Autodesk Fusion 360 part; units mm, degrees
(part 3 of 7)
sketch "Open core spacer (4)" plane through (0, 0, 40.4) normal (0, 0, 1) x (1, 0, 0) in component "CORE | GuardUpper"
  circle A0 centre (0, 0) radius 3.2
extrude "Open core spacer (1)'''" add sketch "Open core spacer (4)" along normal blind 14.6 separate body makes body 8 in component "CORE | GuardUpper"
ref_plane "WorkPlane2" through (0, 0, 40.4) normal (0, 0, 1) x (1, 0, 0) in component "CORE | GuardUpper"
sketch "Metal through bolt clearance (4)" plane through (0, 0, 40.4) normal (0, 0, 1) x (1, 0, 0) in component "CORE | GuardUpper"
  circle A0 centre (0, 0) radius 1.2
extrude "Metal through bolt clearance (1)'''" cut sketch "Metal through bolt clearance (4)" along normal blind 14.6 bodies 8 in component "CORE | GuardUpper"
ref_plane "WorkPlane1" through (0, 0, 15) normal (0, 0, 1) x (1, 0, 0) in component "CORE | GuardTall"
sketch "Open core spacer (5)" plane through (0, 0, 15) normal (0, 0, 1) x (1, 0, 0) in component "CORE | GuardTall"
  circle A0 centre (0, 0) radius 3.2
extrude "Open core spacer (1)''''" add sketch "Open core spacer (5)" along normal blind 40 separate body makes body 9 in component "CORE | GuardTall"
ref_plane "WorkPlane2" through (0, 0, 15) normal (0, 0, 1) x (1, 0, 0) in component "CORE | GuardTall"
sketch "Metal through bolt clearance (5)" plane through (0, 0, 15) normal (0, 0, 1) x (1, 0, 0) in component "CORE | GuardTall"
  circle A0 centre (0, 0) radius 1.2
extrude "Metal through bolt clearance (1)''''" cut sketch "Metal through bolt clearance (5)" along normal blind 40 bodies 9 in component "CORE | GuardTall"
ref_plane "WorkPlane1" through (0, 0, 38) normal (0, 0, 1) x (1, 0, 0) in component "CORE | CoreBridge"
sketch "Feather board saddle" plane through (0, 0, 38) normal (0, 0, 1) x (1, 0, 0) in component "CORE | CoreBridge"
  line L0 (-27.5, -13.5) -> (27.5, -13.5)
  line L1 (27.5, -13.5) -> (27.5, 13.5)
  line L2 (27.5, 13.5) -> (-27.5, 13.5)
  line L3 (-27.5, 13.5) -> (-27.5, -13.5)
extrude "Feather board saddle (1)" add sketch "Feather board saddle" along normal blind 2.4 separate body makes body 10 in component "CORE | CoreBridge"
ref_plane "WorkPlane2" through (0, 0, 38) normal (0, 0, 1) x (1, 0, 0) in component "CORE | CoreBridge"
sketch "Raised bridge arm outside servo plugs" plane through (0, 0, 38) normal (0, 0, 1) x (1, 0, 0) in component "CORE | CoreBridge"
  line L0 (38.5978, 18.6998) -> (39.1173, 19.354)
  line L1 (39.1173, 19.354) -> (39.4498, 20.1204)
  line L2 (39.4498, 20.1204) -> (39.5726, 20.9466)
  line L3 (39.5726, 20.9466) -> (39.4774, 21.7766)
  line L4 (39.4774, 21.7766) -> (39.1706, 22.5536)
  line L5 (39.1706, 22.5536) -> (38.6732, 23.2247)
  line L6 (38.6732, 23.2247) -> (38.019, 23.7442)
  line L7 (38.019, 23.7442) -> (37.2527, 24.0767)
  line L8 (37.2527, 24.0767) -> (36.4264, 24.1996)
  line L9 (36.4264, 24.1996) -> (35.5965, 24.1043)
  line L10 (35.5965, 24.1043) -> (34.8195, 23.7976)
  line L11 (34.8195, 23.7976) -> (34.1484, 23.3002)
  line L12 (34.1484, 23.3002) -> (22.7753, 12.3002)
  line L13 (22.7753, 12.3002) -> (22.2558, 11.646)
  line L14 (22.2558, 11.646) -> (21.9233, 10.8796)
  line L15 (21.9233, 10.8796) -> (21.8004, 10.0534)
  line L16 (21.8004, 10.0534) -> (21.8957, 9.2234)
  line L17 (21.8957, 9.2234) -> (22.2024, 8.4464)
  line L18 (22.2024, 8.4464) -> (22.6998, 7.7753)
  line L19 (22.6998, 7.7753) -> (23.354, 7.2558)
  line L20 (23.354, 7.2558) -> (24.1204, 6.9233)
  line L21 (24.1204, 6.9233) -> (24.9466, 6.8004)
  line L22 (24.9466, 6.8004) -> (25.7766, 6.8957)
  line L23 (25.7766, 6.8957) -> (26.5536, 7.2024)
  line L24 (26.5536, 7.2024) -> (27.2247, 7.6998)
  line L25 (27.2247, 7.6998) -> (38.5978, 18.6998)
extrude "Raised bridge arm outside servo plugs (1)" add sketch "Raised bridge arm outside servo plugs" along normal blind 2.4 bodies 10 in component "CORE | CoreBridge"
ref_plane "WorkPlane3" through (0, 0, 38) normal (0, 0, 1) x (1, 0, 0) in component "CORE | CoreBridge"
sketch "Raised bridge arm outside servo plugs (1)" plane through (0, 0, 38) normal (0, 0, 1) x (1, 0, 0) in component "CORE | CoreBridge"
  line L0 (-34.1484, 23.3002) -> (-34.8195, 23.7976)
  line L1 (-34.8195, 23.7976) -> (-35.5965, 24.1043)
  line L2 (-35.5965, 24.1043) -> (-36.4264, 24.1996)
  line L3 (-36.4264, 24.1996) -> (-37.2527, 24.0767)
  line L4 (-37.2527, 24.0767) -> (-38.019, 23.7442)
  line L5 (-38.019, 23.7442) -> (-38.6732, 23.2247)
  line L6 (-38.6732, 23.2247) -> (-39.1706, 22.5536)
  line L7 (-39.1706, 22.5536) -> (-39.4774, 21.7766)
  line L8 (-39.4774, 21.7766) -> (-39.5726, 20.9466)
  line L9 (-39.5726, 20.9466) -> (-39.4498, 20.1204)
  line L10 (-39.4498, 20.1204) -> (-39.1173, 19.354)
  line L11 (-39.1173, 19.354) -> (-38.5978, 18.6998)
  line L12 (-38.5978, 18.6998) -> (-27.2247, 7.6998)
  line L13 (-27.2247, 7.6998) -> (-26.5536, 7.2024)
  line L14 (-26.5536, 7.2024) -> (-25.7766, 6.8957)
  line L15 (-25.7766, 6.8957) -> (-24.9466, 6.8004)
  line L16 (-24.9466, 6.8004) -> (-24.1204, 6.9233)
  line L17 (-24.1204, 6.9233) -> (-23.354, 7.2558)
  line L18 (-23.354, 7.2558) -> (-22.6998, 7.7753)
  line L19 (-22.6998, 7.7753) -> (-22.2024, 8.4464)
  line L20 (-22.2024, 8.4464) -> (-21.8957, 9.2234)
  line L21 (-21.8957, 9.2234) -> (-21.8004, 10.0534)
  line L22 (-21.8004, 10.0534) -> (-21.9233, 10.8796)
  line L23 (-21.9233, 10.8796) -> (-22.2558, 11.646)
  line L24 (-22.2558, 11.646) -> (-22.7753, 12.3002)
  line L25 (-22.7753, 12.3002) -> (-34.1484, 23.3002)
extrude "Raised bridge arm outside servo plugs (2)" add sketch "Raised bridge arm outside servo plugs (1)" along normal blind 2.4 bodies 10 in component "CORE | CoreBridge"
ref_plane "WorkPlane4" through (0, 0, 38) normal (0, 0, 1) x (1, 0, 0) in component "CORE | CoreBridge"
sketch "Raised bridge arm outside servo plugs (2)" plane through (0, 0, 38) normal (0, 0, 1) x (1, 0, 0) in component "CORE | CoreBridge"
  line L0 (-38.5978, -18.6998) -> (-39.1173, -19.354)
  line L1 (-39.1173, -19.354) -> (-39.4498, -20.1204)
  line L2 (-39.4498, -20.1204) -> (-39.5726, -20.9466)
  line L3 (-39.5726, -20.9466) -> (-39.4774, -21.7766)
  line L4 (-39.4774, -21.7766) -> (-39.1706, -22.5536)
  line L5 (-39.1706, -22.5536) -> (-38.6732, -23.2247)
  line L6 (-38.6732, -23.2247) -> (-38.019, -23.7442)
  line L7 (-38.019, -23.7442) -> (-37.2527, -24.0767)
  line L8 (-37.2527, -24.0767) -> (-36.4264, -24.1996)
  line L9 (-36.4264, -24.1996) -> (-35.5965, -24.1043)
  line L10 (-35.5965, -24.1043) -> (-34.8195, -23.7976)
  line L11 (-34.8195, -23.7976) -> (-34.1484, -23.3002)
  line L12 (-34.1484, -23.3002) -> (-22.7753, -12.3002)
  line L13 (-22.7753, -12.3002) -> (-22.2558, -11.646)
  line L14 (-22.2558, -11.646) -> (-21.9233, -10.8796)
  line L15 (-21.9233, -10.8796) -> (-21.8004, -10.0534)
  line L16 (-21.8004, -10.0534) -> (-21.8957, -9.2234)
  line L17 (-21.8957, -9.2234) -> (-22.2024, -8.4464)
  line L18 (-22.2024, -8.4464) -> (-22.6998, -7.7753)
  line L19 (-22.6998, -7.7753) -> (-23.354, -7.2558)
  line L20 (-23.354, -7.2558) -> (-24.1204, -6.9233)
  line L21 (-24.1204, -6.9233) -> (-24.9466, -6.8004)
  line L22 (-24.9466, -6.8004) -> (-25.7766, -6.8957)
  line L23 (-25.7766, -6.8957) -> (-26.5536, -7.2024)
  line L24 (-26.5536, -7.2024) -> (-27.2247, -7.6998)
  line L25 (-27.2247, -7.6998) -> (-38.5978, -18.6998)
extrude "Raised bridge arm outside servo plugs (3)" add sketch "Raised bridge arm outside servo plugs (2)" along normal blind 2.4 bodies 10 in component "CORE | CoreBridge"
ref_plane "WorkPlane5" through (0, 0, 38) normal (0, 0, 1) x (1, 0, 0) in component "CORE | CoreBridge"
sketch "Raised bridge arm outside servo plugs (3)" plane through (0, 0, 38) normal (0, 0, 1) x (1, 0, 0) in component "CORE | CoreBridge"
  line L0 (34.1484, -23.3002) -> (34.8195, -23.7976)
  line L1 (34.8195, -23.7976) -> (35.5965, -24.1043)
  line L2 (35.5965, -24.1043) -> (36.4264, -24.1996)
  line L3 (36.4264, -24.1996) -> (37.2527, -24.0767)
  line L4 (37.2527, -24.0767) -> (38.019, -23.7442)
  line L5 (38.019, -23.7442) -> (38.6732, -23.2247)
  line L6 (38.6732, -23.2247) -> (39.1706, -22.5536)
  line L7 (39.1706, -22.5536) -> (39.4774, -21.7766)
  line L8 (39.4774, -21.7766) -> (39.5726, -20.9466)
  line L9 (39.5726, -20.9466) -> (39.4498, -20.1204)
  line L10 (39.4498, -20.1204) -> (39.1173, -19.354)
  line L11 (39.1173, -19.354) -> (38.5978, -18.6998)
  line L12 (38.5978, -18.6998) -> (27.2247, -7.6998)
  line L13 (27.2247, -7.6998) -> (26.5536, -7.2024)
  line L14 (26.5536, -7.2024) -> (25.7766, -6.8957)
  line L15 (25.7766, -6.8957) -> (24.9466, -6.8004)
  line L16 (24.9466, -6.8004) -> (24.1204, -6.9233)
  line L17 (24.1204, -6.9233) -> (23.354, -7.2558)
  line L18 (23.354, -7.2558) -> (22.6998, -7.7753)
  line L19 (22.6998, -7.7753) -> (22.2024, -8.4464)
  line L20 (22.2024, -8.4464) -> (21.8957, -9.2234)
  line L21 (21.8957, -9.2234) -> (21.8004, -10.0534)
  line L22 (21.8004, -10.0534) -> (21.9233, -10.8796)
  line L23 (21.9233, -10.8796) -> (22.2558, -11.646)
  line L24 (22.2558, -11.646) -> (22.7753, -12.3002)
  line L25 (22.7753, -12.3002) -> (34.1484, -23.3002)
extrude "Raised bridge arm outside servo plugs (4)" add sketch "Raised bridge arm outside servo plugs (3)" along normal blind 2.4 bodies 10 in component "CORE | CoreBridge"
ref_plane "WorkPlane6" through (0, 0, 40.4) normal (0, 0, 1) x (1, 0, 0) in component "CORE | CoreBridge"
sketch "Feather exact M2 standoff" plane through (0, 0, 40.4) normal (0, 0, 1) x (1, 0, 0) in component "CORE | CoreBridge"
  circle A0 centre (-22.86, -8.89) radius 2.8
extrude "Feather exact M2 standoff (1)" add sketch "Feather exact M2 standoff" along normal blind 4 bodies 10 in component "CORE | CoreBridge"
ref_plane "WorkPlane7" through (0, 0, 40.4) normal (0, 0, 1) x (1, 0, 0) in component "CORE | CoreBridge"
sketch "Feather exact M2 standoff (1)" plane through (0, 0, 40.4) normal (0, 0, 1) x (1, 0, 0) in component "CORE | CoreBridge"
  circle A0 centre (-22.86, 8.89) radius 2.8
extrude "Feather exact M2 standoff (2)" add sketch "Feather exact M2 standoff (1)" along normal blind 4 bodies 10 in component "CORE | CoreBridge"
ref_plane "WorkPlane8" through (0, 0, 40.4) normal (0, 0, 1) x (1, 0, 0) in component "CORE | CoreBridge"
sketch "Feather exact M2 standoff (2)" plane through (0, 0, 40.4) normal (0, 0, 1) x (1, 0, 0) in component "CORE | CoreBridge"
  circle A0 centre (22.86, -8.89) radius 2.8
extrude "Feather exact M2 standoff (3)" add sketch "Feather exact M2 standoff (2)" along normal blind 4 bodies 10 in component "CORE | CoreBridge"
ref_plane "WorkPlane9" through (0, 0, 40.4) normal (0, 0, 1) x (1, 0, 0) in component "CORE | CoreBridge"
sketch "Feather exact M2 standoff (3)" plane through (0, 0, 40.4) normal (0, 0, 1) x (1, 0, 0) in component "CORE | CoreBridge"
  circle A0 centre (22.86, 8.89) radius 2.8
extrude "Feather exact M2 standoff (4)" add sketch "Feather exact M2 standoff (3)" along normal blind 4 bodies 10 in component "CORE | CoreBridge"
ref_plane "WorkPlane10" through (0, 0, 38) normal (0, 0, 1) x (1, 0, 0) in component "CORE | CoreBridge"
sketch "Separate logic buck cradle" plane through (0, 0, 38) normal (0, 0, 1) x (1, 0, 0) in component "CORE | CoreBridge"
  line L0 (-11, 13) -> (11, 13)
  line L1 (11, 13) -> (11, 29)
  line L2 (11, 29) -> (-11, 29)
  line L3 (-11, 29) -> (-11, 13)
extrude "Separate logic buck cradle (1)" add sketch "Separate logic buck cradle" along normal blind 2.4 bodies 10 in component "CORE | CoreBridge"
ref_plane "WorkPlane11" through (0, 0, 40.4) normal (0, 0, 1) x (1, 0, 0) in component "CORE | CoreBridge"
sketch "Logic buck side rail" plane through (0, 0, 40.4) normal (0, 0, 1) x (1, 0, 0) in component "CORE | CoreBridge"
  line L0 (-10.9, 14.4) -> (-8.9, 14.4)
  line L1 (-8.9, 14.4) -> (-8.9, 28.6)
  line L2 (-8.9, 28.6) -> (-10.9, 28.6)
  line L3 (-10.9, 28.6) -> (-10.9, 14.4)
extrude "Logic buck side rail (1)" add sketch "Logic buck side rail" along normal blind 2 bodies 10 in component "CORE | CoreBridge"
ref_plane "WorkPlane12" through (0, 0, 40.4) normal (0, 0, 1) x (1, 0, 0) in component "CORE | CoreBridge"
sketch "Logic buck side rail (1)" plane through (0, 0, 40.4) normal (0, 0, 1) x (1, 0, 0) in component "CORE | CoreBridge"
  line L0 (8.9, 14.4) -> (10.9, 14.4)
  line L1 (10.9, 14.4) -> (10.9, 28.6)
  line L2 (10.9, 28.6) -> (8.9, 28.6)
  line L3 (8.9, 28.6) -> (8.9, 14.4)
extrude "Logic buck side rail (2)" add sketch "Logic buck side rail (1)" along normal blind 2 bodies 10 in component "CORE | CoreBridge"
ref_plane "WorkPlane13" through (0, 0, 38) normal (0, 0, 1) x (1, 0, 0) in component "CORE | CoreBridge"
sketch "Vent slots and logic buck retaining strap" plane through (0, 0, 38) normal (0, 0, 1) x (1, 0, 0) in component "CORE | CoreBridge"
  circle A0 centre (36.3731, 21) radius 1.2
  circle A1 centre (-36.3731, 21) radius 1.2
  circle A2 centre (-36.3731, -21) radius 1.2
  circle A3 centre (36.3731, -21) radius 1.2
  line L0 (17, -4) -> (18.0353, -3.8637)
  line L1 (18.0353, -3.8637) -> (19, -3.4641)
  line L2 (19, -3.4641) -> (19.8284, -2.8284)
  line L3 (19.8284, -2.8284) -> (20.4641, -2)
  line L4 (20.4641, -2) -> (20.8637, -1.0353)
  line L5 (20.8637, -1.0353) -> (21, 0)
  line L6 (21, 0) -> (20.8637, 1.0353)
  line L7 (20.8637, 1.0353) -> (20.4641, 2)
  line L8 (20.4641, 2) -> (19.8284, 2.8284)
  line L9 (19.8284, 2.8284) -> (19, 3.4641)
  line L10 (19, 3.4641) -> (18.0353, 3.8637)
  line L11 (18.0353, 3.8637) -> (17, 4)
  line L12 (17, 4) -> (-17, 4)
  line L13 (-17, 4) -> (-18.0353, 3.8637)
  line L14 (-18.0353, 3.8637) -> (-19, 3.4641)
  line L15 (-19, 3.4641) -> (-19.8284, 2.8284)
  line L16 (-19.8284, 2.8284) -> (-20.4641, 2)
  line L17 (-20.4641, 2) -> (-20.8637, 1.0353)
  line L18 (-20.8637, 1.0353) -> (-21, 0)
  line L19 (-21, 0) -> (-20.8637, -1.0353)
  line L20 (-20.8637, -1.0353) -> (-20.4641, -2)
  line L21 (-20.4641, -2) -> (-19.8284, -2.8284)
  line L22 (-19.8284, -2.8284) -> (-19, -3.4641)
  line L23 (-19, -3.4641) -> (-18.0353, -3.8637)
  line L24 (-18.0353, -3.8637) -> (-17, -4)
  line L25 (-17, -4) -> (17, -4)
  line L26 (8, 24.8) -> (8.3106, 24.8409)
  line L27 (8.3106, 24.8409) -> (8.6, 24.9608)
  line L28 (8.6, 24.9608) -> (8.8485, 25.1515)
  line L29 (8.8485, 25.1515) -> (9.0392, 25.4)
  line L30 (9.0392, 25.4) -> (9.1591, 25.6894)
  line L31 (9.1591, 25.6894) -> (9.2, 26)
  line L32 (9.2, 26) -> (9.1591, 26.3106)
  line L33 (9.1591, 26.3106) -> (9.0392, 26.6)
  line L34 (9.0392, 26.6) -> (8.8485, 26.8485)
  line L35 (8.8485, 26.8485) -> (8.6, 27.0392)
  line L36 (8.6, 27.0392) -> (8.3106, 27.1591)
  line L37 (8.3106, 27.1591) -> (8, 27.2)
  line L38 (8, 27.2) -> (-8, 27.2)
  line L39 (-8, 27.2) -> (-8.3106, 27.1591)
  line L40 (-8.3106, 27.1591) -> (-8.6, 27.0392)
  line L41 (-8.6, 27.0392) -> (-8.8485, 26.8485)
  line L42 (-8.8485, 26.8485) -> (-9.0392, 26.6)
  line L43 (-9.0392, 26.6) -> (-9.1591, 26.3106)
  line L44 (-9.1591, 26.3106) -> (-9.2, 26)
  line L45 (-9.2, 26) -> (-9.1591, 25.6894)
  line L46 (-9.1591, 25.6894) -> (-9.0392, 25.4)
  line L47 (-9.0392, 25.4) -> (-8.8485, 25.1515)
  line L48 (-8.8485, 25.1515) -> (-8.6, 24.9608)
  line L49 (-8.6, 24.9608) -> (-8.3106, 24.8409)
  line L50 (-8.3106, 24.8409) -> (-8, 24.8)
  line L51 (-8, 24.8) -> (8, 24.8)
extrude "Vent slots and logic buck retaining strap (1)" cut sketch "Vent slots and logic buck retaining strap" along normal blind 2.4 bodies 10 in component "CORE | CoreBridge"
ref_plane "WorkPlane14" through (0, 0, 38) normal (0, 0, 1) x (1, 0, 0) in component "CORE | CoreBridge"
sketch "Feather M2 through holes" plane through (0, 0, 38) normal (0, 0, 1) x (1, 0, 0) in component "CORE | CoreBridge"
  circle A0 centre (-22.86, -8.89) radius 1.2
  circle A1 centre (-22.86, 8.89) radius 1.2
  circle A2 centre (22.86, -8.89) radius 1.2
  circle A3 centre (22.86, 8.89) radius 1.2
extrude "Feather M2 through holes (1)" cut sketch "Feather M2 through holes" along normal blind 6.4 bodies 10 in component "CORE | CoreBridge"
ref_plane "WorkPlane1" through (0, 0, 55) normal (0, 0, 1) x (1, 0, 0) in component "CORE | CoreCap"
sketch "Removable protective top" plane through (0, 0, 55) normal (0, 0, 1) x (1, 0, 0) in component "CORE | CoreCap"
  line L0 (43.5, 0) -> (43.1279, 5.7432)
  line L1 (43.1279, 5.7432) -> (42.0178, 11.388)
  line L2 (42.0178, 11.388) -> (40.1888, 16.8381)
  line L3 (40.1888, 16.8381) -> (37.6721, 22)
  line L4 (37.6721, 22) -> (34.5109, 26.7855)
  line L5 (34.5109, 26.7855) -> (30.7591, 31.1127)
  line L6 (30.7591, 31.1127) -> (26.4811, 34.9075)
  line L7 (26.4811, 34.9075) -> (21.75, 38.1051)
  line L8 (21.75, 38.1051) -> (16.6467, 40.6507)
  line L9 (16.6467, 40.6507) -> (11.2586, 42.5007)
  line L10 (11.2586, 42.5007) -> (5.6779, 43.6236)
  line L11 (5.6779, 43.6236) -> (0, 44)
  line L12 (0, 44) -> (-5.6779, 43.6236)
  line L13 (-5.6779, 43.6236) -> (-11.2586, 42.5007)
  line L14 (-11.2586, 42.5007) -> (-16.6467, 40.6507)
  line L15 (-16.6467, 40.6507) -> (-21.75, 38.1051)
  line L16 (-21.75, 38.1051) -> (-26.4811, 34.9075)
  line L17 (-26.4811, 34.9075) -> (-30.7591, 31.1127)
  line L18 (-30.7591, 31.1127) -> (-34.5109, 26.7855)
  line L19 (-34.5109, 26.7855) -> (-37.6721, 22)
  line L20 (-37.6721, 22) -> (-40.1888, 16.8381)
  line L21 (-40.1888, 16.8381) -> (-42.0178, 11.388)
  line L22 (-42.0178, 11.388) -> (-43.1279, 5.7432)
  line L23 (-43.1279, 5.7432) -> (-43.5, 0)
  line L24 (-43.5, 0) -> (-43.1279, -5.7432)
  line L25 (-43.1279, -5.7432) -> (-42.0178, -11.388)
  line L26 (-42.0178, -11.388) -> (-40.1888, -16.8381)
  line L27 (-40.1888, -16.8381) -> (-37.6721, -22)
  line L28 (-37.6721, -22) -> (-34.5109, -26.7855)
  line L29 (-34.5109, -26.7855) -> (-30.7591, -31.1127)
  line L30 (-30.7591, -31.1127) -> (-26.4811, -34.9075)
  line L31 (-26.4811, -34.9075) -> (-21.75, -38.1051)
  line L32 (-21.75, -38.1051) -> (-16.6467, -40.6507)
  line L33 (-16.6467, -40.6507) -> (-11.2586, -42.5007)
  line L34 (-11.2586, -42.5007) -> (-5.6779, -43.6236)
  line L35 (-5.6779, -43.6236) -> (0, -44)
  line L36 (0, -44) -> (5.6779, -43.6236)
  line L37 (5.6779, -43.6236) -> (11.2586, -42.5007)
  line L38 (11.2586, -42.5007) -> (16.6467, -40.6507)
  line L39 (16.6467, -40.6507) -> (21.75, -38.1051)
  line L40 (21.75, -38.1051) -> (26.4811, -34.9075)
  line L41 (26.4811, -34.9075) -> (30.7591, -31.1127)
  line L42 (30.7591, -31.1127) -> (34.5109, -26.7855)
  line L43 (34.5109, -26.7855) -> (37.6721, -22)
  line L44 (37.6721, -22) -> (40.1888, -16.8381)
  line L45 (40.1888, -16.8381) -> (42.0178, -11.388)
  line L46 (42.0178, -11.388) -> (43.1279, -5.7432)
  line L47 (43.1279, -5.7432) -> (43.5, 0)
extrude "Removable protective top (1)" add sketch "Removable protective top" along normal blind 2.4 separate body makes body 11 in component "CORE | CoreCap"
ref_plane "WorkPlane2" through (0, 0, 55) normal (0, 0, 1) x (1, 0, 0) in component "CORE | CoreCap"
sketch "Parallel ventilation slots" plane through (0, 0, 55) normal (0, 0, 1) x (1, 0, 0) in component "CORE | CoreCap"
  line L0 (23, -29.6) -> (23.4141, -29.5455)
  line L1 (23.4141, -29.5455) -> (23.8, -29.3856)
  line L2 (23.8, -29.3856) -> (24.1314, -29.1314)
  line L3 (24.1314, -29.1314) -> (24.3856, -28.8)
  line L4 (24.3856, -28.8) -> (24.5455, -28.4141)
  line L5 (24.5455, -28.4141) -> (24.6, -28)
  line L6 (24.6, -28) -> (24.5455, -27.5859)
  line L7 (24.5455, -27.5859) -> (24.3856, -27.2)
  line L8 (24.3856, -27.2) -> (24.1314, -26.8686)
  line L9 (24.1314, -26.8686) -> (23.8, -26.6144)
  line L10 (23.8, -26.6144) -> (23.4141, -26.4545)
  line L11 (23.4141, -26.4545) -> (23, -26.4)
  line L12 (23, -26.4) -> (-23, -26.4)
  line L13 (-23, -26.4) -> (-23.4141, -26.4545)
  line L14 (-23.4141, -26.4545) -> (-23.8, -26.6144)
  line L15 (-23.8, -26.6144) -> (-24.1314, -26.8686)
  line L16 (-24.1314, -26.8686) -> (-24.3856, -27.2)
  line L17 (-24.3856, -27.2) -> (-24.5455, -27.5859)
  line L18 (-24.5455, -27.5859) -> (-24.6, -28)
  line L19 (-24.6, -28) -> (-24.5455, -28.4141)
  line L20 (-24.5455, -28.4141) -> (-24.3856, -28.8)
  line L21 (-24.3856, -28.8) -> (-24.1314, -29.1314)
  line L22 (-24.1314, -29.1314) -> (-23.8, -29.3856)
  line L23 (-23.8, -29.3856) -> (-23.4141, -29.5455)
  line L24 (-23.4141, -29.5455) -> (-23, -29.6)
  line L25 (-23, -29.6) -> (23, -29.6)
extrude "Parallel ventilation slots (1)" cut sketch "Parallel ventilation slots" along normal blind 2.4 bodies 11 in component "CORE | CoreCap"
ref_plane "WorkPlane3" through (0, 0, 55) normal (0, 0, 1) x (1, 0, 0) in component "CORE | CoreCap"
sketch "Parallel ventilation slots (1)" plane through (0, 0, 55) normal (0, 0, 1) x (1, 0, 0) in component "CORE | CoreCap"
  line L0 (28, -21.6) -> (28.4141, -21.5455)
  line L1 (28.4141, -21.5455) -> (28.8, -21.3856)
  line L2 (28.8, -21.3856) -> (29.1314, -21.1314)
  line L3 (29.1314, -21.1314) -> (29.3856, -20.8)
  line L4 (29.3856, -20.8) -> (29.5455, -20.4141)
  line L5 (29.5455, -20.4141) -> (29.6, -20)
  line L6 (29.6, -20) -> (29.5455, -19.5859)
  line L7 (29.5455, -19.5859) -> (29.3856, -19.2)
  line L8 (29.3856, -19.2) -> (29.1314, -18.8686)
  line L9 (29.1314, -18.8686) -> (28.8, -18.6144)
  line L10 (28.8, -18.6144) -> (28.4141, -18.4545)
  line L11 (28.4141, -18.4545) -> (28, -18.4)
  line L12 (28, -18.4) -> (-28, -18.4)
  line L13 (-28, -18.4) -> (-28.4141, -18.4545)
  line L14 (-28.4141, -18.4545) -> (-28.8, -18.6144)
  line L15 (-28.8, -18.6144) -> (-29.1314, -18.8686)
  line L16 (-29.1314, -18.8686) -> (-29.3856, -19.2)
  line L17 (-29.3856, -19.2) -> (-29.5455, -19.5859)
  line L18 (-29.5455, -19.5859) -> (-29.6, -20)
  line L19 (-29.6, -20) -> (-29.5455, -20.4141)
  line L20 (-29.5455, -20.4141) -> (-29.3856, -20.8)
  line L21 (-29.3856, -20.8) -> (-29.1314, -21.1314)
  line L22 (-29.1314, -21.1314) -> (-28.8, -21.3856)
  line L23 (-28.8, -21.3856) -> (-28.4141, -21.5455)
  line L24 (-28.4141, -21.5455) -> (-28, -21.6)
  line L25 (-28, -21.6) -> (28, -21.6)
extrude "Parallel ventilation slots (2)" cut sketch "Parallel ventilation slots (1)" along normal blind 2.4 bodies 11 in component "CORE | CoreCap"
ref_plane "WorkPlane4" through (0, 0, 55) normal (0, 0, 1) x (1, 0, 0) in component "CORE | CoreCap"
sketch "Parallel ventilation slots (2)" plane through (0, 0, 55) normal (0, 0, 1) x (1, 0, 0) in component "CORE | CoreCap"
  line L0 (28, -13.6) -> (28.4141, -13.5455)
  line L1 (28.4141, -13.5455) -> (28.8, -13.3856)
  line L2 (28.8, -13.3856) -> (29.1314, -13.1314)
  line L3 (29.1314, -13.1314) -> (29.3856, -12.8)
  line L4 (29.3856, -12.8) -> (29.5455, -12.4141)
  line L5 (29.5455, -12.4141) -> (29.6, -12)
  line L6 (29.6, -12) -> (29.5455, -11.5859)
  line L7 (29.5455, -11.5859) -> (29.3856, -11.2)
  line L8 (29.3856, -11.2) -> (29.1314, -10.8686)
  line L9 (29.1314, -10.8686) -> (28.8, -10.6144)
  line L10 (28.8, -10.6144) -> (28.4141, -10.4545)
  line L11 (28.4141, -10.4545) -> (28, -10.4)
  line L12 (28, -10.4) -> (-28, -10.4)
  line L13 (-28, -10.4) -> (-28.4141, -10.4545)
  line L14 (-28.4141, -10.4545) -> (-28.8, -10.6144)
  line L15 (-28.8, -10.6144) -> (-29.1314, -10.8686)
  line L16 (-29.1314, -10.8686) -> (-29.3856, -11.2)
  line L17 (-29.3856, -11.2) -> (-29.5455, -11.5859)
  line L18 (-29.5455, -11.5859) -> (-29.6, -12)
  line L19 (-29.6, -12) -> (-29.5455, -12.4141)
  line L20 (-29.5455, -12.4141) -> (-29.3856, -12.8)
  line L21 (-29.3856, -12.8) -> (-29.1314, -13.1314)
  line L22 (-29.1314, -13.1314) -> (-28.8, -13.3856)
  line L23 (-28.8, -13.3856) -> (-28.4141, -13.5455)
  line L24 (-28.4141, -13.5455) -> (-28, -13.6)
  line L25 (-28, -13.6) -> (28, -13.6)
extrude "Parallel ventilation slots (3)" cut sketch "Parallel ventilation slots (2)" along normal blind 2.4 bodies 11 in component "CORE | CoreCap"
ref_plane "WorkPlane5" through (0, 0, 55) normal (0, 0, 1) x (1, 0, 0) in component "CORE | CoreCap"
sketch "Parallel ventilation slots (3)" plane through (0, 0, 55) normal (0, 0, 1) x (1, 0, 0) in component "CORE | CoreCap"
  line L0 (28, -1.6) -> (28.4141, -1.5455)
  line L1 (28.4141, -1.5455) -> (28.8, -1.3856)
  line L2 (28.8, -1.3856) -> (29.1314, -1.1314)
  line L3 (29.1314, -1.1314) -> (29.3856, -0.8)
  line L4 (29.3856, -0.8) -> (29.5455, -0.4141)
  line L5 (29.5455, -0.4141) -> (29.6, 0)
  line L6 (29.6, 0) -> (29.5455, 0.4141)
  line L7 (29.5455, 0.4141) -> (29.3856, 0.8)
  line L8 (29.3856, 0.8) -> (29.1314, 1.1314)
  line L9 (29.1314, 1.1314) -> (28.8, 1.3856)
  line L10 (28.8, 1.3856) -> (28.4141, 1.5455)
  line L11 (28.4141, 1.5455) -> (28, 1.6)
  line L12 (28, 1.6) -> (-28, 1.6)
  line L13 (-28, 1.6) -> (-28.4141, 1.5455)
  line L14 (-28.4141, 1.5455) -> (-28.8, 1.3856)
  line L15 (-28.8, 1.3856) -> (-29.1314, 1.1314)
  line L16 (-29.1314, 1.1314) -> (-29.3856, 0.8)
  line L17 (-29.3856, 0.8) -> (-29.5455, 0.4141)
  line L18 (-29.5455, 0.4141) -> (-29.6, 0)
  line L19 (-29.6, 0) -> (-29.5455, -0.4141)
  line L20 (-29.5455, -0.4141) -> (-29.3856, -0.8)
  line L21 (-29.3856, -0.8) -> (-29.1314, -1.1314)
  line L22 (-29.1314, -1.1314) -> (-28.8, -1.3856)
  line L23 (-28.8, -1.3856) -> (-28.4141, -1.5455)
  line L24 (-28.4141, -1.5455) -> (-28, -1.6)
  line L25 (-28, -1.6) -> (28, -1.6)
extrude "Parallel ventilation slots (4)" cut sketch "Parallel ventilation slots (3)" along normal blind 2.4 bodies 11 in component "CORE | CoreCap"
ref_plane "WorkPlane6" through (0, 0, 55) normal (0, 0, 1) x (1, 0, 0) in component "CORE | CoreCap"
sketch "Parallel ventilation slots (4)" plane through (0, 0, 55) normal (0, 0, 1) x (1, 0, 0) in component "CORE | CoreCap"
  line L0 (28, 10.4) -> (28.4141, 10.4545)
  line L1 (28.4141, 10.4545) -> (28.8, 10.6144)
  line L2 (28.8, 10.6144) -> (29.1314, 10.8686)
  line L3 (29.1314, 10.8686) -> (29.3856, 11.2)
  line L4 (29.3856, 11.2) -> (29.5455, 11.5859)
  line L5 (29.5455, 11.5859) -> (29.6, 12)
  line L6 (29.6, 12) -> (29.5455, 12.4141)
  line L7 (29.5455, 12.4141) -> (29.3856, 12.8)
  line L8 (29.3856, 12.8) -> (29.1314, 13.1314)
  line L9 (29.1314, 13.1314) -> (28.8, 13.3856)
  line L10 (28.8, 13.3856) -> (28.4141, 13.5455)
  line L11 (28.4141, 13.5455) -> (28, 13.6)
  line L12 (28, 13.6) -> (-28, 13.6)
  line L13 (-28, 13.6) -> (-28.4141, 13.5455)
  line L14 (-28.4141, 13.5455) -> (-28.8, 13.3856)
  line L15 (-28.8, 13.3856) -> (-29.1314, 13.1314)
  line L16 (-29.1314, 13.1314) -> (-29.3856, 12.8)
  line L17 (-29.3856, 12.8) -> (-29.5455, 12.4141)
  line L18 (-29.5455, 12.4141) -> (-29.6, 12)
  line L19 (-29.6, 12) -> (-29.5455, 11.5859)
  line L20 (-29.5455, 11.5859) -> (-29.3856, 11.2)
  line L21 (-29.3856, 11.2) -> (-29.1314, 10.8686)
  line L22 (-29.1314, 10.8686) -> (-28.8, 10.6144)
  line L23 (-28.8, 10.6144) -> (-28.4141, 10.4545)
  line L24 (-28.4141, 10.4545) -> (-28, 10.4)
  line L25 (-28, 10.4) -> (28, 10.4)
extrude "Parallel ventilation slots (5)" cut sketch "Parallel ventilation slots (4)" along normal blind 2.4 bodies 11 in component "CORE | CoreCap"
ref_plane "WorkPlane7" through (0, 0, 55) normal (0, 0, 1) x (1, 0, 0) in component "CORE | CoreCap"
sketch "Parallel ventilation slots (5)" plane through (0, 0, 55) normal (0, 0, 1) x (1, 0, 0) in component "CORE | CoreCap"
  line L0 (28, 18.4) -> (28.4141, 18.4545)
  line L1 (28.4141, 18.4545) -> (28.8, 18.6144)
  line L2 (28.8, 18.6144) -> (29.1314, 18.8686)
  line L3 (29.1314, 18.8686) -> (29.3856, 19.2)
  line L4 (29.3856, 19.2) -> (29.5455, 19.5859)
  line L5 (29.5455, 19.5859) -> (29.6, 20)
  line L6 (29.6, 20) -> (29.5455, 20.4141)
  line L7 (29.5455, 20.4141) -> (29.3856, 20.8)
  line L8 (29.3856, 20.8) -> (29.1314, 21.1314)
  line L9 (29.1314, 21.1314) -> (28.8, 21.3856)
  line L10 (28.8, 21.3856) -> (28.4141, 21.5455)
  line L11 (28.4141, 21.5455) -> (28, 21.6)
  line L12 (28, 21.6) -> (-28, 21.6)
  line L13 (-28, 21.6) -> (-28.4141, 21.5455)
  line L14 (-28.4141, 21.5455) -> (-28.8, 21.3856)
  line L15 (-28.8, 21.3856) -> (-29.1314, 21.1314)
  line L16 (-29.1314, 21.1314) -> (-29.3856, 20.8)
  line L17 (-29.3856, 20.8) -> (-29.5455, 20.4141)
  line L18 (-29.5455, 20.4141) -> (-29.6, 20)
  line L19 (-29.6, 20) -> (-29.5455, 19.5859)
  line L20 (-29.5455, 19.5859) -> (-29.3856, 19.2)
  line L21 (-29.3856, 19.2) -> (-29.1314, 18.8686)
  line L22 (-29.1314, 18.8686) -> (-28.8, 18.6144)
  line L23 (-28.8, 18.6144) -> (-28.4141, 18.4545)
  line L24 (-28.4141, 18.4545) -> (-28, 18.4)
  line L25 (-28, 18.4) -> (28, 18.4)
extrude "Parallel ventilation slots (6)" cut sketch "Parallel ventilation slots (5)" along normal blind 2.4 bodies 11 in component "CORE | CoreCap"
ref_plane "WorkPlane8" through (0, 0, 55) normal (0, 0, 1) x (1, 0, 0) in component "CORE | CoreCap"
sketch "Parallel ventilation slots (6)" plane through (0, 0, 55) normal (0, 0, 1) x (1, 0, 0) in component "CORE | CoreCap"
  line L0 (23, 26.4) -> (23.4141, 26.4545)
  line L1 (23.4141, 26.4545) -> (23.8, 26.6144)
  line L2 (23.8, 26.6144) -> (24.1314, 26.8686)
  line L3 (24.1314, 26.8686) -> (24.3856, 27.2)
  line L4 (24.3856, 27.2) -> (24.5455, 27.5859)
  line L5 (24.5455, 27.5859) -> (24.6, 28)
  line L6 (24.6, 28) -> (24.5455, 28.4141)
  line L7 (24.5455, 28.4141) -> (24.3856, 28.8)
  line L8 (24.3856, 28.8) -> (24.1314, 29.1314)
  line L9 (24.1314, 29.1314) -> (23.8, 29.3856)
  line L10 (23.8, 29.3856) -> (23.4141, 29.5455)
  line L11 (23.4141, 29.5455) -> (23, 29.6)
  line L12 (23, 29.6) -> (-23, 29.6)
  line L13 (-23, 29.6) -> (-23.4141, 29.5455)
  line L14 (-23.4141, 29.5455) -> (-23.8, 29.3856)
  line L15 (-23.8, 29.3856) -> (-24.1314, 29.1314)
  line L16 (-24.1314, 29.1314) -> (-24.3856, 28.8)
  line L17 (-24.3856, 28.8) -> (-24.5455, 28.4141)
  line L18 (-24.5455, 28.4141) -> (-24.6, 28)
  line L19 (-24.6, 28) -> (-24.5455, 27.5859)
  line L20 (-24.5455, 27.5859) -> (-24.3856, 27.2)
  line L21 (-24.3856, 27.2) -> (-24.1314, 26.8686)
  line L22 (-24.1314, 26.8686) -> (-23.8, 26.6144)
  line L23 (-23.8, 26.6144) -> (-23.4141, 26.4545)
  line L24 (-23.4141, 26.4545) -> (-23, 26.4)
  line L25 (-23, 26.4) -> (23, 26.4)
extrude "Parallel ventilation slots (7)" cut sketch "Parallel ventilation slots (6)" along normal blind 2.4 bodies 11 in component "CORE | CoreCap"
ref_plane "WorkPlane9" through (0, 0, 55) normal (0, 0, 1) x (1, 0, 0) in component "CORE | CoreCap"
sketch "Removable M2x50 guard fasteners" plane through (0, 0, 55) normal (0, 0, 1) x (1, 0, 0) in component "CORE | CoreCap"
  circle A0 centre (36.3731, 21) radius 1.2
  circle A1 centre (0, 42) radius 1.2
  circle A2 centre (-36.3731, 21) radius 1.2
  circle A3 centre (-36.3731, -21) radius 1.2
  circle A4 centre (0, -42) radius 1.2
  circle A5 centre (36.3731, -21) radius 1.2
extrude "Removable M2x50 guard fasteners (1)" cut sketch "Removable M2x50 guard fasteners" along normal blind 2.4 bodies 11 in component "CORE | CoreCap"
ref_plane "WorkPlane1" through (0, 0, 4) normal (0, 0, 1) x (1, 0, 0) in component "03 | Coxa yaw plate"
sketch "Rounded coxa hub" plane through (0, 0, 4) normal (0, 0, 1) x (1, 0, 0) in component "03 | Coxa yaw plate"
  circle A0 centre (0, 0) radius 13.5
extrude "Rounded coxa hub (1)" add sketch "Rounded coxa hub" along normal blind 3 separate body makes body 12 in component "03 | Coxa yaw plate"
ref_plane "WorkPlane2" through (0, 0, 4) normal (0, 0, 1) x (1, 0, 0) in component "03 | Coxa yaw plate"
sketch "Tapered coxa carrier" plane through (0, 0, 4) normal (0, 0, 1) x (1, 0, 0) in component "03 | Coxa yaw plate"
  line L0 (0, -13.5) -> (15, -12)
  line L1 (15, -12) -> (46, -8.5)
  line L2 (46, -8.5) -> (46, 8.5)
  line L3 (46, 8.5) -> (15, 12)
  line L4 (15, 12) -> (0, 13.5)
  line L5 (0, 13.5) -> (0, -13.5)
extrude "Tapered coxa carrier (1)" add sketch "Tapered coxa carrier" along normal blind 3 bodies 12 in component "03 | Coxa yaw plate"
ref_plane "WorkPlane3" through (0, 0, 4) normal (0, 0, 1) x (1, 0, 0) in component "03 | Coxa yaw plate"
sketch "Stock horn screw access and adjustable M2 slots" plane through (0, 0, 4) normal (0, 0, 1) x (1, 0, 0) in component "03 | Coxa yaw plate"
  circle A0 centre (0, 0) radius 2.6
  line L0 (10.7, -1.2) -> (11.0106, -1.1591)
  line L1 (11.0106, -1.1591) -> (11.3, -1.0392)
  line L2 (11.3, -1.0392) -> (11.5485, -0.8485)
  line L3 (11.5485, -0.8485) -> (11.7392, -0.6)
  line L4 (11.7392, -0.6) -> (11.8591, -0.3106)
  line L5 (11.8591, -0.3106) -> (11.9, 0)
  line L6 (11.9, 0) -> (11.8591, 0.3106)
  line L7 (11.8591, 0.3106) -> (11.7392, 0.6)
  line L8 (11.7392, 0.6) -> (11.5485, 0.8485)
  line L9 (11.5485, 0.8485) -> (11.3, 1.0392)
  line L10 (11.3, 1.0392) -> (11.0106, 1.1591)
  line L11 (11.0106, 1.1591) -> (10.7, 1.2)
  line L12 (10.7, 1.2) -> (6.8, 1.2)
  line L13 (6.8, 1.2) -> (6.4894, 1.1591)
  line L14 (6.4894, 1.1591) -> (6.2, 1.0392)
  line L15 (6.2, 1.0392) -> (5.9515, 0.8485)
  line L16 (5.9515, 0.8485) -> (5.7608, 0.6)
  line L17 (5.7608, 0.6) -> (5.6409, 0.3106)
  line L18 (5.6409, 0.3106) -> (5.6, 0)
  line L19 (5.6, 0) -> (5.6409, -0.3106)
  line L20 (5.6409, -0.3106) -> (5.7608, -0.6)
  line L21 (5.7608, -0.6) -> (5.9515, -0.8485)
  line L22 (5.9515, -0.8485) -> (6.2, -1.0392)
  line L23 (6.2, -1.0392) -> (6.4894, -1.1591)
  line L24 (6.4894, -1.1591) -> (6.8, -1.2)
  line L25 (6.8, -1.2) -> (10.7, -1.2)
  line L26 (-6.8, -1.2) -> (-6.4894, -1.1591)
  line L27 (-6.4894, -1.1591) -> (-6.2, -1.0392)
  line L28 (-6.2, -1.0392) -> (-5.9515, -0.8485)
  line L29 (-5.9515, -0.8485) -> (-5.7608, -0.6)
  line L30 (-5.7608, -0.6) -> (-5.6409, -0.3106)
  line L31 (-5.6409, -0.3106) -> (-5.6, 0)
  line L32 (-5.6, 0) -> (-5.6409, 0.3106)
  line L33 (-5.6409, 0.3106) -> (-5.7608, 0.6)
  line L34 (-5.7608, 0.6) -> (-5.9515, 0.8485)
  line L35 (-5.9515, 0.8485) -> (-6.2, 1.0392)
  line L36 (-6.2, 1.0392) -> (-6.4894, 1.1591)
  line L37 (-6.4894, 1.1591) -> (-6.8, 1.2)
  line L38 (-6.8, 1.2) -> (-10.7, 1.2)
  line L39 (-10.7, 1.2) -> (-11.0106, 1.1591)
  line L40 (-11.0106, 1.1591) -> (-11.3, 1.0392)
  line L41 (-11.3, 1.0392) -> (-11.5485, 0.8485)
  line L42 (-11.5485, 0.8485) -> (-11.7392, 0.6)
  line L43 (-11.7392, 0.6) -> (-11.8591, 0.3106)
  line L44 (-11.8591, 0.3106) -> (-11.9, 0)
  line L45 (-11.9, 0) -> (-11.8591, -0.3106)
  line L46 (-11.8591, -0.3106) -> (-11.7392, -0.6)
  line L47 (-11.7392, -0.6) -> (-11.5485, -0.8485)
  line L48 (-11.5485, -0.8485) -> (-11.3, -1.0392)
  line L49 (-11.3, -1.0392) -> (-11.0106, -1.1591)
  line L50 (-11.0106, -1.1591) -> (-10.7, -1.2)
  line L51 (-10.7, -1.2) -> (-6.8, -1.2)
extrude "Stock horn screw access and adjustable M2 slots (1)" cut sketch "Stock horn screw access and adjustable M2 slots" along normal blind 3 bodies 12 in component "03 | Coxa yaw plate"
ref_plane "WorkPlane4" through (0, 0, 4) normal (0, 0, 1) x (1, 0, 0) in component "03 | Coxa yaw plate"
sketch "Hip bracket bolts and lightening" plane through (0, 0, 4) normal (0, 0, 1) x (1, 0, 0) in component "03 | Coxa yaw plate"
  circle A0 centre (17, 4) radius 1.7
  circle A1 centre (42, 4) radius 1.7
  line L0 (35, -8.5) -> (35.647, -8.4148)
  line L1 (35.647, -8.4148) -> (36.25, -8.1651)
  line L2 (36.25, -8.1651) -> (36.7678, -7.7678)
  line L3 (36.7678, -7.7678) -> (37.1651, -7.25)
  line L4 (37.1651, -7.25) -> (37.4148, -6.647)
  line L5 (37.4148, -6.647) -> (37.5, -6)
  line L6 (37.5, -6) -> (37.4148, -5.353)
  line L7 (37.4148, -5.353) -> (37.1651, -4.75)
  line L8 (37.1651, -4.75) -> (36.7678, -4.2322)
  line L9 (36.7678, -4.2322) -> (36.25, -3.8349)
  line L10 (36.25, -3.8349) -> (35.647, -3.5852)
  line L11 (35.647, -3.5852) -> (35, -3.5)
  line L12 (35, -3.5) -> (16, -3.5)
  line L13 (16, -3.5) -> (15.353, -3.5852)
  line L14 (15.353, -3.5852) -> (14.75, -3.8349)
  line L15 (14.75, -3.8349) -> (14.2322, -4.2322)
  line L16 (14.2322, -4.2322) -> (13.8349, -4.75)
  line L17 (13.8349, -4.75) -> (13.5852, -5.353)
  line L18 (13.5852, -5.353) -> (13.5, -6)
  line L19 (13.5, -6) -> (13.5852, -6.647)
  line L20 (13.5852, -6.647) -> (13.8349, -7.25)
  line L21 (13.8349, -7.25) -> (14.2322, -7.7678)
  line L22 (14.2322, -7.7678) -> (14.75, -8.1651)
  line L23 (14.75, -8.1651) -> (15.353, -8.4148)
  line L24 (15.353, -8.4148) -> (16, -8.5)
  line L25 (16, -8.5) -> (35, -8.5)
extrude "Hip bracket bolts and lightening (1)" cut sketch "Hip bracket bolts and lightening" along normal blind 3 bodies 12 in component "03 | Coxa yaw plate"
ref_plane "WorkPlane1" through (0, 0, 7) normal (0, 0, 1) x (1, 0, 0) in component "04 | Hip removable servo bracket"
sketch "Flat mounting foot" plane through (0, 0, 7) normal (0, 0, 1) x (1, 0, 0) in component "04 | Hip removable servo bracket"
  line L0 (8, -11) -> (46, -11)
  line L1 (46, -11) -> (46, 8)
  line L2 (46, 8) -> (8, 8)
  line L3 (8, 8) -> (8, -11)
extrude "Flat mounting foot (1)" add sketch "Flat mounting foot" along normal blind 3 separate body makes body 13 in component "04 | Hip removable servo bracket"
ref_plane "WorkPlane2" through (0, -9, 0) normal (0, 1, 0) x (0, 0, 1) in component "04 | Hip removable servo bracket"
sketch "Upright servo mounting frame" plane through (0, -9, 0) normal (0, 1, 0) x (1, 0, 0) in component "04 | Hip removable servo bracket"
  line L0 (8, -10) -> (46, -10)
  line L1 (46, -10) -> (46, -50)
  line L2 (46, -50) -> (8, -50)
  line L3 (8, -50) -> (8, -10)
extrude "Upright servo mounting frame (1)" add sketch "Upright servo mounting frame" along normal blind 3 bodies 13 in component "04 | Hip removable servo bracket"
ref_plane "WorkPlane3" through (0, -9, 0) normal (0, 1, 0) x (0, 0, 1) in component "04 | Hip removable servo bracket"
sketch "MG90S shoulder clearance" plane through (0, -9, 0) normal (0, 1, 0) x (1, 0, 0) in component "04 | Hip removable servo bracket"
  line L0 (13.7, -31.5) -> (37.1, -31.5)
  line L1 (37.1, -31.5) -> (37.1, -51)
  line L2 (37.1, -51) -> (13.7, -51)
  line L3 (13.7, -51) -> (13.7, -31.5)
extrude "MG90S shoulder clearance (1)" cut sketch "MG90S shoulder clearance" along normal blind 3 bodies 13 in component "04 | Hip removable servo bracket"
ref_plane "WorkPlane4" through (0, -9, 0) normal (0, 1, 0) x (0, 0, 1) in component "04 | Hip removable servo bracket"
sketch "Shoulder ear mounting slots" plane through (0, -9, 0) normal (0, 1, 0) x (1, 0, 0) in component "04 | Hip removable servo bracket"
  line L0 (12.6, -36.8) -> (12.9106, -36.8409)
  line L1 (12.9106, -36.8409) -> (13.2, -36.9608)
  line L2 (13.2, -36.9608) -> (13.4485, -37.1515)
  line L3 (13.4485, -37.1515) -> (13.6392, -37.4)
  line L4 (13.6392, -37.4) -> (13.7591, -37.6894)
  line L5 (13.7591, -37.6894) -> (13.8, -38)
  line L6 (13.8, -38) -> (13.7591, -38.3106)
  line L7 (13.7591, -38.3106) -> (13.6392, -38.6)
  line L8 (13.6392, -38.6) -> (13.4485, -38.8485)
  line L9 (13.4485, -38.8485) -> (13.2, -39.0392)
  line L10 (13.2, -39.0392) -> (12.9106, -39.1591)
  line L11 (12.9106, -39.1591) -> (12.6, -39.2)
  line L12 (12.6, -39.2) -> (10.4, -39.2)
  line L13 (10.4, -39.2) -> (10.0894, -39.1591)
  line L14 (10.0894, -39.1591) -> (9.8, -39.0392)
  line L15 (9.8, -39.0392) -> (9.5515, -38.8485)
  line L16 (9.5515, -38.8485) -> (9.3608, -38.6)
  line L17 (9.3608, -38.6) -> (9.2409, -38.3106)
  line L18 (9.2409, -38.3106) -> (9.2, -38)
  line L19 (9.2, -38) -> (9.2409, -37.6894)
  line L20 (9.2409, -37.6894) -> (9.3608, -37.4)
  line L21 (9.3608, -37.4) -> (9.5515, -37.1515)
  line L22 (9.5515, -37.1515) -> (9.8, -36.9608)
  line L23 (9.8, -36.9608) -> (10.0894, -36.8409)
  line L24 (10.0894, -36.8409) -> (10.4, -36.8)
  line L25 (10.4, -36.8) -> (12.6, -36.8)
  line L26 (40.4, -36.8) -> (40.7106, -36.8409)
  line L27 (40.7106, -36.8409) -> (41, -36.9608)
  line L28 (41, -36.9608) -> (41.2485, -37.1515)
  line L29 (41.2485, -37.1515) -> (41.4392, -37.4)
  line L30 (41.4392, -37.4) -> (41.5591, -37.6894)
  line L31 (41.5591, -37.6894) -> (41.6, -38)
  line L32 (41.6, -38) -> (41.5591, -38.3106)
  line L33 (41.5591, -38.3106) -> (41.4392, -38.6)
  line L34 (41.4392, -38.6) -> (41.2485, -38.8485)
  line L35 (41.2485, -38.8485) -> (41, -39.0392)
  line L36 (41, -39.0392) -> (40.7106, -39.1591)
  line L37 (40.7106, -39.1591) -> (40.4, -39.2)
  line L38 (40.4, -39.2) -> (38.2, -39.2)
  line L39 (38.2, -39.2) -> (37.8894, -39.1591)
  line L40 (37.8894, -39.1591) -> (37.6, -39.0392)
  line L41 (37.6, -39.0392) -> (37.3515, -38.8485)
  line L42 (37.3515, -38.8485) -> (37.1608, -38.6)
  line L43 (37.1608, -38.6) -> (37.0409, -38.3106)
  line L44 (37.0409, -38.3106) -> (37, -38)
  line L45 (37, -38) -> (37.0409, -37.6894)
  line L46 (37.0409, -37.6894) -> (37.1608, -37.4)
  line L47 (37.1608, -37.4) -> (37.3515, -37.1515)
  line L48 (37.3515, -37.1515) -> (37.6, -36.9608)
  line L49 (37.6, -36.9608) -> (37.8894, -36.8409)
  line L50 (37.8894, -36.8409) -> (38.2, -36.8)
  line L51 (38.2, -36.8) -> (40.4, -36.8)
extrude "Shoulder ear mounting slots (1)" cut sketch "Shoulder ear mounting slots" along normal blind 3 bodies 13 in component "04 | Hip removable servo bracket"
ref_plane "WorkPlane5" through (0, 0, 7) normal (0, 0, 1) x (1, 0, 0) in component "04 | Hip removable servo bracket"
sketch "M3 mounting foot holes" plane through (0, 0, 7) normal (0, 0, 1) x (1, 0, 0) in component "04 | Hip removable servo bracket"
  circle A0 centre (17, 4) radius 1.7
  circle A1 centre (42, 4) radius 1.7
extrude "M3 mounting foot holes (1)" cut sketch "M3 mounting foot holes" along normal blind 3 bodies 13 in component "04 | Hip removable servo bracket"
ref_plane "WorkPlane6" through (0, -9, 0) normal (0, 1, 0) x (0, 0, 1) in component "04 | Hip removable servo bracket"
sketch "Self-supporting lightening window" plane through (0, -9, 0) normal (0, 1, 0) x (1, 0, 0) in component "04 | Hip removable servo bracket"
  line L0 (19, -12) -> (32, -12)
  line L1 (32, -12) -> (32, -19.5)
  line L2 (32, -19.5) -> (25.5, -26)
  line L3 (25.5, -26) -> (19, -19.5)
  line L4 (19, -19.5) -> (19, -12)
extrude "Self-supporting lightening window (1)" cut sketch "Self-supporting lightening window" along normal blind 3 bodies 13 in component "04 | Hip removable servo bracket"
ref_plane "WorkPlane7" through (0, 0, 7) normal (0, 0, 1) x (1, 0, 0) in component "04 | Hip removable servo bracket"
sketch "Yaw horn nut and tool access" plane through (0, 0, 7) normal (0, 0, 1) x (1, 0, 0) in component "04 | Hip removable servo bracket"
  circle A0 centre (8.5, 0) radius 3
extrude "Yaw horn nut and tool access (1)" cut sketch "Yaw horn nut and tool access" along normal blind 3 bodies 13 in component "04 | Hip removable servo bracket"
ref_plane "WorkPlane8" through (0, 0, 8.5) normal (0, 0, 1) x (1, 0, 0) in component "04 | Hip removable servo bracket"
sketch "M3 90 degree countersink section" plane through (0, 0, 8.5) normal (0, 0, 1) x (1, 0, 0) in component "04 | Hip removable servo bracket"
  circle A0 centre (17, 4) radius 1.7
ref_plane "WorkPlane9" through (0, 0, 10) normal (0, 0, 1) x (1, 0, 0) in component "04 | Hip removable servo bracket"
sketch "M3 90 degree countersink section (1)" plane through (0, 0, 10) normal (0, 0, 1) x (1, 0, 0) in component "04 | Hip removable servo bracket"
  circle A0 centre (17, 4) radius 3.2
loft "M3 90 degree countersink" cut profiles "M3 90 degree countersink section", "M3 90 degree countersink section (1)" section 1 section 2 bodies 13 in component "04 | Hip removable servo bracket"
ref_plane "WorkPlane10" through (0, 0, 8.5) normal (0, 0, 1) x (1, 0, 0) in component "04 | Hip removable servo bracket"
sketch "M3 90 degree countersink section (2)" plane through (0, 0, 8.5) normal (0, 0, 1) x (1, 0, 0) in component "04 | Hip removable servo bracket"
  circle A0 centre (42, 4) radius 1.7
ref_plane "WorkPlane11" through (0, 0, 10) normal (0, 0, 1) x (1, 0, 0) in component "04 | Hip removable servo bracket"
sketch "M3 90 degree countersink section (3)" plane through (0, 0, 10) normal (0, 0, 1) x (1, 0, 0) in component "04 | Hip removable servo bracket"
  circle A0 centre (42, 4) radius 3.2
loft "M3 90 degree countersink (1)" cut profiles "M3 90 degree countersink section (2)", "M3 90 degree countersink section (3)" section 1 section 2 bodies 13 in component "04 | Hip removable servo bracket"
ref_plane "WorkPlane1" through (0, 4, 0) normal (0, 1, 0) x (0, 0, 1) in component "05 | Femur horn link"
sketch "Femur plate" plane through (0, 4, 0) normal (0, 1, 0) x (1, 0, 0) in component "05 | Femur horn link"
  line L0 (22.5, 13.5) -> (25.9941, 13.04)
  line L1 (25.9941, 13.04) -> (29.25, 11.6913)
  line L2 (29.25, 11.6913) -> (32.0459, 9.5459)
  line L3 (32.0459, 9.5459) -> (34.1913, 6.75)
  line L4 (34.1913, 6.75) -> (35.54, 3.4941)
  line L5 (35.54, 3.4941) -> (36, 0)
  line L6 (36, 0) -> (35.54, -3.4941)
  line L7 (35.54, -3.4941) -> (34.1913, -6.75)
  line L8 (34.1913, -6.75) -> (32.0459, -9.5459)
  line L9 (32.0459, -9.5459) -> (29.25, -11.6913)
  line L10 (29.25, -11.6913) -> (25.9941, -13.04)
  line L11 (25.9941, -13.04) -> (22.5, -13.5)
  line L12 (22.5, -13.5) -> (0, -13.5)
  line L13 (0, -13.5) -> (-3.4941, -13.04)
  line L14 (-3.4941, -13.04) -> (-6.75, -11.6913)
  line L15 (-6.75, -11.6913) -> (-9.5459, -9.5459)
  line L16 (-9.5459, -9.5459) -> (-11.6913, -6.75)
  line L17 (-11.6913, -6.75) -> (-13.04, -3.4941)
  line L18 (-13.04, -3.4941) -> (-13.5, 0)
  line L19 (-13.5, 0) -> (-13.04, 3.4941)
  line L20 (-13.04, 3.4941) -> (-11.6913, 6.75)
  line L21 (-11.6913, 6.75) -> (-9.5459, 9.5459)
  line L22 (-9.5459, 9.5459) -> (-6.75, 11.6913)
  line L23 (-6.75, 11.6913) -> (-3.4941, 13.04)
  line L24 (-3.4941, 13.04) -> (0, 13.5)
  line L25 (0, 13.5) -> (22.5, 13.5)
extrude "Femur plate (1)" add sketch "Femur plate" along normal blind 3 separate body makes body 14 in component "05 | Femur horn link"
ref_plane "WorkPlane2" through (0, 4, 0) normal (0, 1, 0) x (0, 0, 1) in component "05 | Femur horn link"
sketch "Stock horn screw access and adjustable M2 slots (2)" plane through (0, 4, 0) normal (0, 1, 0) x (1, 0, 0) in component "05 | Femur horn link"
  circle A0 centre (0, 0) radius 2.6
  line L0 (10.7, 1.2) -> (11.0106, 1.1591)
  line L1 (11.0106, 1.1591) -> (11.3, 1.0392)
  line L2 (11.3, 1.0392) -> (11.5485, 0.8485)
  line L3 (11.5485, 0.8485) -> (11.7392, 0.6)
  line L4 (11.7392, 0.6) -> (11.8591, 0.3106)
  line L5 (11.8591, 0.3106) -> (11.9, 0)
  line L6 (11.9, 0) -> (11.8591, -0.3106)
  line L7 (11.8591, -0.3106) -> (11.7392, -0.6)
  line L8 (11.7392, -0.6) -> (11.5485, -0.8485)
  line L9 (11.5485, -0.8485) -> (11.3, -1.0392)
  line L10 (11.3, -1.0392) -> (11.0106, -1.1591)
  line L11 (11.0106, -1.1591) -> (10.7, -1.2)
  line L12 (10.7, -1.2) -> (6.8, -1.2)
  line L13 (6.8, -1.2) -> (6.4894, -1.1591)
  line L14 (6.4894, -1.1591) -> (6.2, -1.0392)
  line L15 (6.2, -1.0392) -> (5.9515, -0.8485)
  line L16 (5.9515, -0.8485) -> (5.7608, -0.6)
  line L17 (5.7608, -0.6) -> (5.6409, -0.3106)
  line L18 (5.6409, -0.3106) -> (5.6, 0)
  line L19 (5.6, 0) -> (5.6409, 0.3106)
  line L20 (5.6409, 0.3106) -> (5.7608, 0.6)
  line L21 (5.7608, 0.6) -> (5.9515, 0.8485)
  line L22 (5.9515, 0.8485) -> (6.2, 1.0392)
  line L23 (6.2, 1.0392) -> (6.4894, 1.1591)
  line L24 (6.4894, 1.1591) -> (6.8, 1.2)
  line L25 (6.8, 1.2) -> (10.7, 1.2)
  line L26 (-6.8, 1.2) -> (-6.4894, 1.1591)
  line L27 (-6.4894, 1.1591) -> (-6.2, 1.0392)
  line L28 (-6.2, 1.0392) -> (-5.9515, 0.8485)
  line L29 (-5.9515, 0.8485) -> (-5.7608, 0.6)
  line L30 (-5.7608, 0.6) -> (-5.6409, 0.3106)
  line L31 (-5.6409, 0.3106) -> (-5.6, 0)
  line L32 (-5.6, 0) -> (-5.6409, -0.3106)
  line L33 (-5.6409, -0.3106) -> (-5.7608, -0.6)
  line L34 (-5.7608, -0.6) -> (-5.9515, -0.8485)
  line L35 (-5.9515, -0.8485) -> (-6.2, -1.0392)
  line L36 (-6.2, -1.0392) -> (-6.4894, -1.1591)
  line L37 (-6.4894, -1.1591) -> (-6.8, -1.2)
  line L38 (-6.8, -1.2) -> (-10.7, -1.2)
  line L39 (-10.7, -1.2) -> (-11.0106, -1.1591)
  line L40 (-11.0106, -1.1591) -> (-11.3, -1.0392)
  line L41 (-11.3, -1.0392) -> (-11.5485, -0.8485)
  line L42 (-11.5485, -0.8485) -> (-11.7392, -0.6)
  line L43 (-11.7392, -0.6) -> (-11.8591, -0.3106)
  line L44 (-11.8591, -0.3106) -> (-11.9, 0)
  line L45 (-11.9, 0) -> (-11.8591, 0.3106)
  line L46 (-11.8591, 0.3106) -> (-11.7392, 0.6)
  line L47 (-11.7392, 0.6) -> (-11.5485, 0.8485)
  line L48 (-11.5485, 0.8485) -> (-11.3, 1.0392)
  line L49 (-11.3, 1.0392) -> (-11.0106, 1.1591)
  line L50 (-11.0106, 1.1591) -> (-10.7, 1.2)
  line L51 (-10.7, 1.2) -> (-6.8, 1.2)
extrude "Stock horn screw access and adjustable M2 slots (1)'" cut sketch "Stock horn screw access and adjustable M2 slots (2)" along normal blind 3 bodies 14 in component "05 | Femur horn link"
ref_plane "WorkPlane3" through (0, 4, 0) normal (0, 1, 0) x (0, 0, 1) in component "05 | Femur horn link"
sketch "Knee mount fastening and lightening" plane through (0, 4, 0) normal (0, 1, 0) x (1, 0, 0) in component "05 | Femur horn link"
  circle A0 centre (22.5, 10) radius 1.2
  circle A1 centre (22.5, -10) radius 1.2
  line L0 (25, 4) -> (25.5176, 3.9319)
  line L1 (25.5176, 3.9319) -> (26, 3.7321)
  line L2 (26, 3.7321) -> (26.4142, 3.4142)
  line L3 (26.4142, 3.4142) -> (26.7321, 3)
  line L4 (26.7321, 3) -> (26.9319, 2.5176)
  line L5 (26.9319, 2.5176) -> (27, 2)
  line L6 (27, 2) -> (26.9319, 1.4824)
  line L7 (26.9319, 1.4824) -> (26.7321, 1)
  line L8 (26.7321, 1) -> (26.4142, 0.5858)
  line L9 (26.4142, 0.5858) -> (26, 0.2679)
  line L10 (26, 0.2679) -> (25.5176, 0.0681)
  line L11 (25.5176, 0.0681) -> (25, 0)
  line L12 (25, 0) -> (15, 0)
  line L13 (15, 0) -> (14.4824, 0.0681)
  line L14 (14.4824, 0.0681) -> (14, 0.2679)
  line L15 (14, 0.2679) -> (13.5858, 0.5858)
  line L16 (13.5858, 0.5858) -> (13.2679, 1)
  line L17 (13.2679, 1) -> (13.0681, 1.4824)
  line L18 (13.0681, 1.4824) -> (13, 2)
  line L19 (13, 2) -> (13.0681, 2.5176)
  line L20 (13.0681, 2.5176) -> (13.2679, 3)
  line L21 (13.2679, 3) -> (13.5858, 3.4142)
  line L22 (13.5858, 3.4142) -> (14, 3.7321)
  line L23 (14, 3.7321) -> (14.4824, 3.9319)
  line L24 (14.4824, 3.9319) -> (15, 4)
  line L25 (15, 4) -> (25, 4)